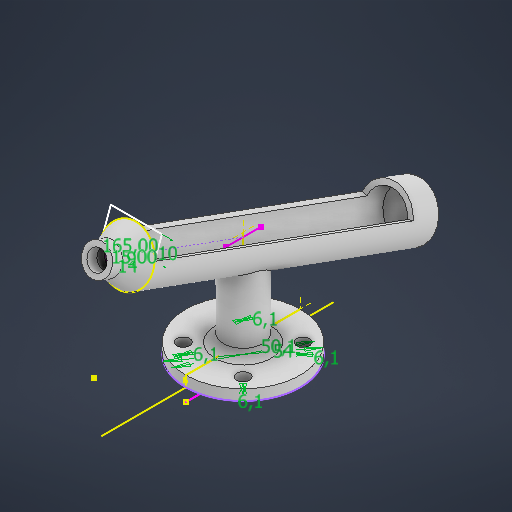
# Autodesk Inventor part: roboticasintecho
Saved by Autodesk Inventor 2027.1 (Build 311270010, 270A)
## iProperties
Created: 2026-09-15
Part Number: roboticasintecho
Material: Genérico
Document SubType Name: Modeling
Designer: FELIPE
Density: 1 g/cm^3
Appearance: Valor por defecto
Author: FELIPE
Autodesk Inventor part; units mm, degrees
ref_plane "YZ Plane" through (0, 0, 0) normal (1, 0, 0) x (0, 1, 0)
ref_plane "XZ Plane" through (0, 0, 0) normal (0, 1, 0) x (-1, 0, 0)
sketch "Boceto1" plane through (0, 0, 0) normal (0, 1, 0) x (-1, 0, 0)
  circle A0 centre (0, 0) radius 25.05
  circle A1 centre (0, 0) radius 27
  line L0 (0, 0) -> (20, 0) construction
  line L1 (0, 0) -> (20, 0) construction
  line L2 (0, 0) -> (20, 0) construction
  line L3 (0, 0) -> (21.5442, 0) construction
  line L4 (0, 0) -> (20, 0) construction
  circle A2 centre (14.1421, 14.1421) radius 3.05
  circle A3 centre (14.1421, -14.1421) radius 3.05
  circle A4 centre (-14.1421, 14.1421) radius 3.05
  circle A5 centre (-14.1421, -14.1421) radius 3.05
  dimension "d0" = 50.1
  dimension "d2" = 54
  dimension "d8" = 6.1
  dimension "d9" = 6.1
  dimension "d10" = 6.1
  dimension "d11" = 6.1
  constraints: 10 end point, 6 centre point, 5 horizontal, 1 coincident
  measures "d0" diameter of A0
  measures "d2" diameter of A1
  measures "d8" diameter of A2
  measures "d9" diameter of A3
  measures "d10" diameter of A4
  measures "d11" diameter of A5
extrude "Extrusión1" add sketch "Boceto1" along normal blind 5 contours A0
extrude "Extrusión2" add sketch "Boceto1" along normal blind 5 contours A1
sketch "Boceto2" plane through (0, 5, 0) normal (0, 1, 0) x (1, 0, 0)
  circle A0 centre (0, 0) radius 1.25
  circle A1 centre (0, 0) radius 9.25
  dimension "d18" = 2.5
  dimension "d21" = 18.5
  constraints: 2 centre point, 2 coincident
  measures "d18" diameter of A0
  measures "d21" diameter of A1
sketch "Boceto3" plane through (0, 0, 0) normal (1, 0, 0) x (0, 1, 0)
  line L0 (5, -27) -> (5, 27) projected
  line L1 (5, 0) -> (50, 0)
  line L2 (5, 0) -> (50, 0) construction
  point P0 (0, 0)
  dimension "d19" = 45
  constraints: 4 end point, 2 horizontal, 1 collinear, 1 midpoint
  measures "d19" distance of L1.start L1.end
sketch "Boceto4" plane through (0, 0, 0) normal (1, 0, 0) x (0, 1, 0)
  line L0 (0, 66.7387) -> (0, -42.6231) projected
  line L1 (0, 17.1921) -> (0, 11.0921) projected
  line L2 (0, -11.0921) -> (0, -17.1921) projected
  line L3 (0, 17.1921) -> (0, 11.0921) projected
  line L4 (0, -11.0921) -> (0, -17.1921) projected
  line L5 (5, 17.1921) -> (5, 11.0921) projected
  line L6 (5, -11.0921) -> (5, -17.1921) projected
  line L7 (5, 17.1921) -> (5, 11.0921) projected
  line L8 (5, -11.0921) -> (5, -17.1921) projected
  line L9 (0, 0) -> (0, 0) projected
  line L10 (-6, 0) -> (-6, 0) projected
  line L11 (-6, 0) -> (-6, 0) projected
  line L12 (0, -11.0921) -> (0, -17.1921) projected
  line L13 (0, 17.1921) -> (0, 11.0921) projected
  line L14 (0, -11.0921) -> (0, -17.1921) projected
  line L15 (0, 17.1921) -> (0, 11.0921) projected
  line L16 (5, -11.0921) -> (5, -17.1921) projected
  line L17 (5, 17.1921) -> (5, 11.0921) projected
  line L18 (5, -11.0921) -> (5, -17.1921) projected
  line L19 (5, 17.1921) -> (5, 11.0921) projected
  line L20 (-6, -25.05) -> (-6, 25.05) projected
  line L21 (0, -25.05) -> (0, 25.05) projected
  line L22 (5, -27) -> (5, 27) projected
  line L23 (-6, 27) -> (-6, -27) projected
  line L24 (-6, -25.05) -> (-6, 25.05) projected
  line L25 (5, -11.0921) -> (5, -17.1921) projected
  line L26 (0, -11.0921) -> (0, -17.1921) projected
  line L27 (5, 17.1921) -> (5, 11.0921) projected
  line L28 (0, 17.1921) -> (0, 11.0921) projected
  line L29 (5, -11.0921) -> (5, -17.1921) projected
  line L30 (0, -11.0921) -> (0, -17.1921) projected
  line L31 (5, 17.1921) -> (5, 11.0921) projected
  line L32 (0, 17.1921) -> (0, 11.0921) projected
  line L33 (3, -8.25) -> (3, 8.25) projected
  line L34 (48, -8.25) -> (48, 8.25) projected
  line L35 (5, -27) -> (5, 27) projected
  line L36 (5, 0) -> (50, 0) projected
  line L37 (5, 0) -> (50, 0) construction
  line L38 (68, 54.9495) -> (48, 0) construction
  line L39 (5, -27) -> (0, -27) projected
  line L40 (0, -27) -> (0, 27) projected
  line L41 (0, 27) -> (5, 27) projected
  line L42 (5, 27) -> (5, -27) projected
  point P0 (48, 8.25)
  point P1 (3, -27)
  point P2 (3, 27)
  point P3 (3, 0)
  dimension "d24" = 45
  dimension "d25" = 110
  dimension "d26" = 20
  constraints: 2 end point, 1 point on line, 7 other
  measures "d24" distance of point (3, 0) L38.end
  measures "d25" angle of L36 L38
  measures "d26" horizontal distance of L38.end L38.start
extrude "Extrusión3" add sketch "Boceto2" along normal blind 45
ref_plane "Plano de trabajo2" through (0, 68, 54.9495) normal (0, -0.3420201, -0.9396926) x (1, 0, 0)
sketch "Boceto7" plane through (0, 68, 54.9495) normal (0, -0.3420201, -0.9396926) x (1, 0, 0)
  circle A0 centre (0, 0) radius 12.5
  circle A1 centre (0, 0) radius 10
  point P0 (0, 45.1052)
  point P1 (0, 0)
  dimension "d38" = 25
  dimension "d39" = 20
  constraints: 2 centre point, 2 coincident
  measures "d38" diameter of A0
  measures "d39" diameter of A1
extrude "Extrusión4" add sketch "Boceto7" along normal blind 140
sketch "Boceto8" plane through (0, 68, 54.9495) normal (0, -0.3420201, -0.9396926) x (1, 0, 0)
  circle A0 centre (0, 0) radius 8.25 projected
  circle A1 centre (0, 0) radius 10
  point P0 (0, 45.1052)
  dimension "d44" = 20
  constraints: 1 centre point, 1 coincident
  measures "d44" diameter of A1
extrude "Extrusión5" cut sketch "Boceto8" along normal blind 120 and the other way blind 0.25 contours A0 | A1
sketch "Boceto9" plane through (0, 68, 54.9495) normal (0, -0.3420201, -0.9396926) x (1, 0, 0)
  circle A0 centre (0, 0) radius 8.25 projected
  circle A1 centre (0, 0) radius 9.25 projected
  circle A2 centre (0, 0) radius 4.5
  circle A3 centre (0, 0) radius 7
  point P0 (0, 45.1052)
  dimension "d49" = 9
  dimension "d50" = 14
  constraints: 2 centre point, 2 coincident
  measures "d49" diameter of A2
  measures "d50" diameter of A3
ref_plane "Plano de trabajo3" through (0, 71.4202, 64.3465) normal (0, -0.3420201, -0.9396926) x (1, 0, 0)
sketch "Boceto10" plane through (0, 71.4202, 64.3465) normal (0, -0.3420201, -0.9396926) x (1, 0, 0)
  circle A0 centre (0, 0) radius 7
  point P0 (0, 45.1052)
  dimension "d53" = 14
  constraints: 1 centre point, 1 coincident
  measures "d53" diameter of A0
fillet "Empalme de cara1" radius 4 1 edges at (-9.25, 5, 0)
loft "Solevación1" add profiles "Boceto10" section 1 edges at (-12.5, 68, 54.9495)
sketch "Boceto11" plane through (0, 71.4202, 64.3465) normal (0, -0.3420201, -0.9396926) x (1, 0, 0)
  circle A0 centre (0, 0) radius 7 projected
  circle A1 centre (0, 0) radius 4.5
  point P0 (0, 45.1052)
  dimension "d59" = 9
  constraints: 1 centre point, 1 coincident
  measures "d59" diameter of A1
loft "Solevación2" cut profiles "Boceto11" section 1 edges at (-10, 68, 54.9495) contours A1
sketch "Boceto12" plane through (0, 71.4202, 64.3465) normal (0, -0.3420201, -0.9396926) x (1, 0, 0)
  circle A0 centre (0, 0) radius 4.5 projected
  circle A1 centre (0, 0) radius 7
  circle A2 centre (0, 0) radius 4.5
  point P0 (0, 45.1052)
  dimension "d64" = 14
  dimension "d65" = 9
  constraints: 2 centre point, 2 coincident
  measures "d64" diameter of A1
  measures "d65" diameter of A2
extrude "Extrusión6" add sketch "Boceto12" against normal blind 5
sketch "Boceto14" plane through (0, 68, 54.9495) normal (0, -0.3420201, -0.9396926) x (1, 0, 0)
  circle A0 centre (0, 0) radius 12.5 projected
  line L0 (0, 0) -> (12.0741, -3.2352)
  line L1 (0, 0) -> (12.5, 0) construction
  line L2 (12.0741, -3.2352) -> (12.0741, -13.2352)
  line L3 (0, 0) -> (-12.0741, -3.2352)
  line L4 (0, 0) -> (12.5, 0) construction
  line L5 (-12.0741, -3.2352) -> (-12.0741, -13.2352)
  line L6 (-12.0741, -13.2352) -> (12.0741, -13.2352)
  point P0 (0, 45.1052)
  dimension "d73" = 15
  dimension "d74" = 10
  dimension "d75" = 165
  constraints: 14 end point, 2 equal length, 2 horizontal, 2 point on circle, 2 vertical, 1 perpendicular
  measures "d73" angle of L0 L1
  measures "d74" distance of L0.end L2.end
  measures "d75" angle of L3 L4
extrude "Extrusión8" cut sketch "Boceto14" along normal blind 130 contours L3 L0 A0 | A0 L2 L6 L5 picked at (7.6817, -3.0753)
sketch "Boceto15" plane through (0, 20.1172, -76.6074) normal (0, -0.3420201, -0.9396926) x (-1, 0, 0)
  circle A0 centre (0, 0) radius 12.5 projected
  circle A1 centre (0, 0) radius 12.5
  point P0 (0, -45.1052)
  constraints: 1 centre point, 1 coincident, 1 concentric
extrude "Extrusión9" add sketch "Boceto15" along normal blind 3
fillet "Empalme1" radius 0.2 1 edges at (12.5, 19.0911, -79.4265)
